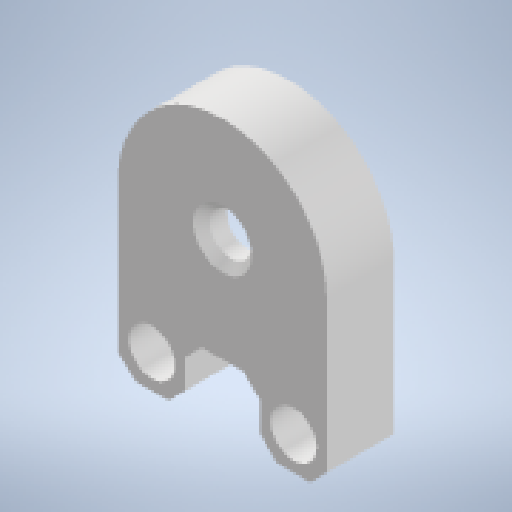
# Autodesk Inventor part: крепление магнита
Saved by Autodesk Inventor 2024.2 (Build 282272000, 272)
## iProperties
Created: 2026-10-27
Part Number: крепление магнита
Material: Типовые
Document SubType Name: Modeling
Designer: katya_notebook
Density: 1 g/cm^3
Appearance: По умолчанию
Author: katya_notebook
Autodesk Inventor part; units mm, degrees
ref_plane "YZ Plane" through (0, 0, 0) normal (1, 0, 0) x (0, 1, 0)
ref_plane "XZ Plane" through (0, 0, 0) normal (0, 1, 0) x (-1, 0, 0)
ref_plane "XY Plane" through (0, 0, 0) normal (0, 0, 1) x (1, 0, 0)
sketch "Эскиз1" plane through (0, 0, 0) normal (0, 0, 1) x (1, 0, 0)
  circle A0 centre (0, 0) radius 12.5
  circle A1 centre (0, 0) radius 10.25
  dimension "d0" = 25
  dimension "d1" = 20.5
  constraints: 2 centre point, 2 coincident
  measures "d0" diameter of A0
  measures "d1" diameter of A1
extrude "Выдавливание1" add sketch "Эскиз1" along normal blind 3 contours A0 | A1
sketch "Эскиз2" plane through (0, 0, 0) normal (0, 0, -1) x (-1, 0, 0)
  circle A0 centre (0, 0) radius 12.5
  circle A1 centre (0, 0) radius 10.25
  dimension "d4" = 25
  dimension "d5" = 20.5
  constraints: 2 centre point, 2 coincident
  measures "d4" diameter of A0
  measures "d5" diameter of A1
extrude "Выдавливание2" add sketch "Эскиз2" along normal blind 5
sketch "Эскиз3" plane through (0, 0, 3) normal (0, 0, 1) x (1, 0, 0)
  circle A0 centre (0, 0) radius 2.5
  dimension "d8" = 5
  constraints: 1 centre point, 1 coincident
  measures "d8" diameter of A0
extrude "Выдавливание3" cut sketch "Эскиз3" against normal blind 5
chamfer "Фаска1" distance 1 angle 45 1 edges at (-2.5, 0, 3)
sketch "Эскиз4" plane through (0, 0, 3) normal (0, 0, 1) x (1, 0, 0)
  circle A0 centre (0, 0) radius 12.5
  line L0 (12.5, 0) -> (12.5, -20)
  line L1 (12.5, -20) -> (4.5, -20)
  line L2 (4.5, -20) -> (4.5, -11.6619)
  line L3 (0, 15.2631) -> (0, -23.3481)
  line L4 (-12.5, 0) -> (-12.5, -20)
  line L5 (-12.5, -20) -> (-4.5, -20)
  line L6 (-4.5, -20) -> (-4.5, -11.6619)
  line L7 (0, -12.5) -> (4.5, -12.5)
  line L8 (0, -12.5) -> (-4.5, -12.5)
  dimension "d14" = 25
  dimension "d15" = 20
  dimension "d16" = 8
  constraints: 18 end point, 4 point on line, 4 symmetric about line, 3 perpendicular, 3 point on circle, 2 vertical, 1 centre point, 1 coincident, 1 tangent
  measures "d14" diameter of A0
  measures "d15" distance of L0.start L0.end
  measures "d16" distance of L0.end L1.end
extrude "Выдавливание4" add sketch "Эскиз4" against normal up to surface (8 mm away) contours A0 L6 L5 L4 | A0 L8 L6 | A0 L2 L7 | L0 L1 L2 A0
chamfer "Фаска2" distance 2 angle 45 6 edges at (4.5, -20, -1) (12.5, -20, -1) (4.5, -12.5, -1) (-4.5, -12.5, -1) (-4.5, -20, -1) (-12.5, -20, -1)
sketch "Эскиз5" plane through (0, 0, 3) normal (0, 0, 1) x (1, 0, 0)
  circle A0 centre (8.5, -16) radius 2.75
  line L0 (-10.5, -20) -> (-12.5, -18) projected
  line L1 (-10.5, -20) -> (-6.5, -20) projected
  line L2 (-4.5, -18) -> (-6.5, -20) projected
  line L3 (-4.5, -18) -> (-4.5, -14.5) projected
  line L4 (-2.5, -12.5) -> (-4.5, -14.5) projected
  line L5 (-2.5, -12.5) -> (2.5, -12.5) projected
  line L6 (4.5, -14.5) -> (2.5, -12.5) projected
  line L7 (4.5, -14.5) -> (4.5, -18) projected
  line L8 (6.5, -20) -> (4.5, -18) projected
  line L9 (6.5, -20) -> (10.5, -20) projected
  line L10 (12.5, -18) -> (10.5, -20) projected
  line L11 (12.5, -18) -> (12.5, 0) projected
  arc A1 (12.5, 0) -> (-12.5, 0) centre (0, 0) ccw projected
  line L12 (-12.5, 0) -> (-12.5, -18) projected
  circle A2 centre (0, 0) radius 3.5 projected
  line L13 (6.5, -20) -> (10.5, -20) projected
  line L14 (0, -21.279) -> (0, 8.0278)
  circle A3 centre (-8.5, -16) radius 2.75
  line L15 (-4.5, -14.5) -> (-4.5, -18)
  line L16 (-6.5, -20) -> (-4.5, -18)
  line L17 (-6.5, -20) -> (-10.5, -20)
  line L18 (-6.5, -20) -> (-10.5, -20)
  point P0 (8.5, -20)
  point P1 (8.5, -20)
  point P2 (8.5, -20)
  point P3 (-8.5, -20)
  point P4 (-8.5, -20)
  point P5 (-8.5, -20)
  dimension "d22" = 5.5
  dimension "d23" = 0
  dimension "d25" = 4
  constraints: 10 end point, 4 symmetric about line, 3 midpoint, 2 centre point, 1 vertical, 1 other
  measures "d22" diameter of A0
  measures "d23" horizontal distance of point (8.5, -20) A0.centre
  measures "d25" distance of point (8.5, -20) A0.centre
extrude "Выдавливание5" cut sketch "Эскиз5" against normal blind 10 contours A0 | A3
